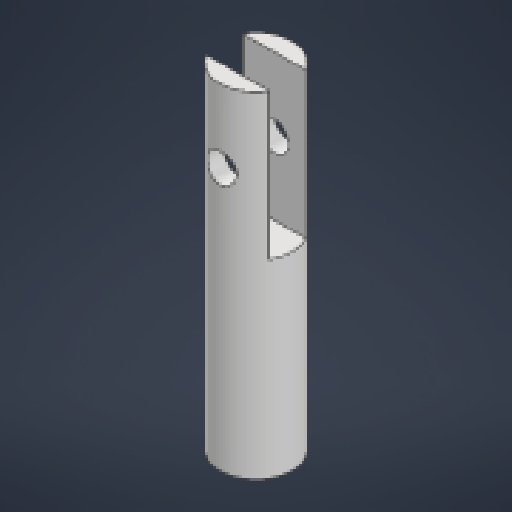
# Autodesk Inventor part: soporteRodillo
Saved by Autodesk Inventor 2027.1 (Build 311270010, 270A)
## iProperties
Created: 2026-11-02
Part Number: soporteRodillo
Material: Genérico
Document SubType Name: Modeling
Designer: MANGEL
Density: 1 g/cm^3
Appearance: Valor por defecto
Author: MANGEL
Autodesk Inventor part; units mm, degrees
ref_plane "YZ Plane" through (0, 0, 0) normal (1, 0, 0) x (0, 1, 0)
ref_plane "XZ Plane" through (0, 0, 0) normal (0, 1, 0) x (-1, 0, 0)
sketch "Boceto1" plane through (0, 0, 0) normal (0, 1, 0) x (-1, 0, 0)
  circle A0 centre (0, 0) radius 5
  dimension "d0" = 10
  constraints: 1 centre point, 1 coincident
  measures "d0" diameter of A0
extrude "Extrusión1" add sketch "Boceto1" along normal blind 46
sketch "Boceto2" plane through (0, 46, 0) normal (0, 1, 0) x (1, 0, 0)
  line L0 (-5.5, -2.5) -> (5.5, -2.5)
  line L1 (5.5, -2.5) -> (5.5, 2.5)
  line L2 (5.5, 2.5) -> (-5.5, 2.5)
  line L3 (-5.5, 2.5) -> (-5.5, -2.5)
  line L4 (-5.5, -2.5) -> (5.5, 2.5) construction
  line L5 (5.5, -2.5) -> (-5.5, 2.5) construction
  point P0 (0, 0)
  dimension "d3" = 5
  dimension "d4" = 11
  constraints: 12 end point, 2 midpoint, 2 parallel, 1 horizontal, 1 perpendicular
  measures "d3" distance between parallel lines of L0 L2
  measures "d4" distance of L1.end L2.end
extrude "Extrusión2" cut sketch "Boceto2" against normal blind 20
ref_plane "Plano de trabajo1" through (-4.3301, 46, 12.5) normal (0, 0, 1) x (1, 0, 0)
sketch "Boceto4" plane through (-4.3301, 46, 12.5) normal (0, 0, 1) x (1, 0, 0)
  circle A0 centre (4.3301, -10) radius 2
  line L0 (0, 0) -> (0, -20) projected
  line L1 (8.6603, 0) -> (0, 0) projected
  point P0 (4.3301, -46)
  point P1 (0, -10)
  point P2 (4.3301, 0)
  dimension "d8" = 4
  constraints: 2 midpoint, 1 centre point, 1 horizontal alignment, 1 vertical alignment
  measures "d8" diameter of A0
extrude "Extrusión3" cut sketch "Boceto4" against normal through all
